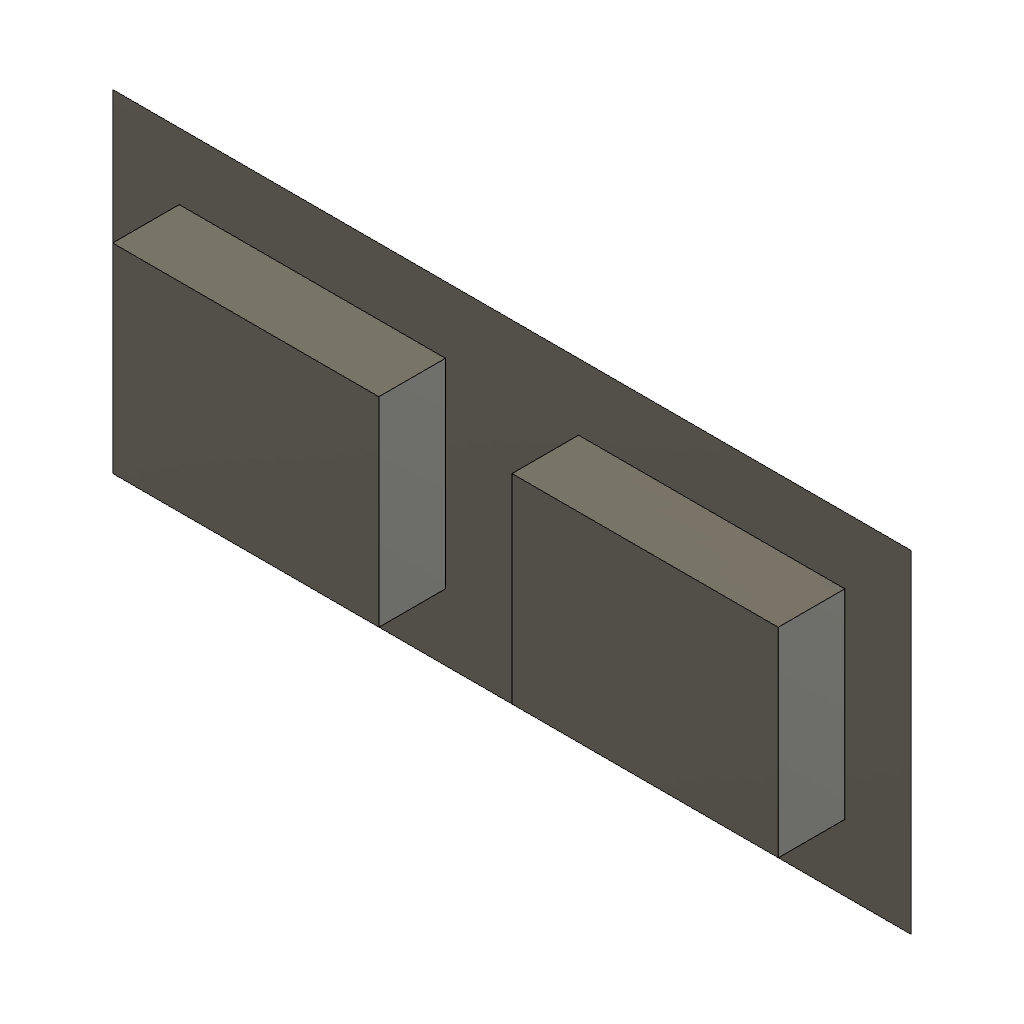
sheet_face_no_extend (Autodesk Fusion 360 design; units mm, degrees)
part number: 2026-10-21-16-23-56-852
Autodesk Fusion 360 part; units mm, degrees
sketch "OwnedMultiSplitBlockSketch_0_sheet_face_no_extend" plane through (0, 0, 0) normal (0, 0, 1) x (1, 0, 0)
  line L0 (0, 0) -> (40, 0)
  line L1 (40, 0) -> (40, 30)
  line L2 (40, 30) -> (0, 30)
  line L3 (0, 30) -> (0, 0)
extrude "OwnedMultiSplitBlockExtrude_0_sheet_face_no_extend" add sketch "OwnedMultiSplitBlockSketch_0_sheet_face_no_extend" along normal blind 20 makes body 1
sketch "OwnedMultiSplitBlockSketch_1_sheet_face_no_extend" plane through (0, 0, 0) normal (0, 0, 1) x (1, 0, 0)
  line L0 (60, 0) -> (100, 0)
  line L1 (100, 0) -> (100, 30)
  line L2 (100, 30) -> (60, 30)
  line L3 (60, 30) -> (60, 0)
extrude "OwnedMultiSplitBlockExtrude_1_sheet_face_no_extend" add sketch "OwnedMultiSplitBlockSketch_1_sheet_face_no_extend" along normal blind 20 separate body makes body 2
ref_plane "WorkPlane1" through (0, 0, 10) normal (0, 0, 1) x (1, 0, 0)
sketch "OwnedSplitPatchBoundary_sheet_face_no_extend" plane through (0, 0, 10) normal (0, 0, 1) x (1, 0, 0)
  line L0 (-10, -10) -> (110, -10)
  line L1 (110, -10) -> (110, 40)
  line L2 (110, 40) -> (-10, 40)
  line L3 (-10, 40) -> (-10, -10)
surface "OwnedSplitToolPatch_sheet_face_no_extend" add patch profiles "OwnedSplitPatchBoundary_sheet_face_no_extend" section 1 separate body makes body 3
split "OwnedSplitBodyMultiSheet_sheet_face_no_extend" by plane through (0, 0, 10) normal (0, 0, 1) bodies 1 2 makes body 5 at (73.3333, 20, 20) makes body 4 at (13.3333, 20, 20)
named bodies: "OwnedMultiSplitBlock_0_sheet_face_no_extend", "OwnedMultiSplitBlock_1_sheet_face_no_extend", "OwnedSplitToolSheet_sheet_face_no_extend", "OwnedMultiSplitBlock_0_sheet_face_no_extend (1)", "OwnedMultiSplitBlock_1_sheet_face_no_extend (1)"
